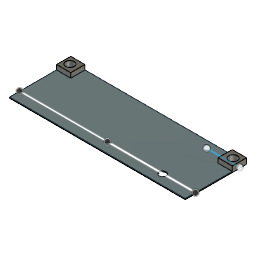
Main board mount - left (Autodesk Fusion 360 design; units mm, degrees)
Autodesk Fusion 360 part; units mm, degrees
sketch "Sketch1" plane through (0, 0, 0) normal (0, 0, 1) x (1, 0, 0)
  line L0 (0, 0) -> (86, 0)
  line L1 (86, 0) -> (86, 30)
  line L2 (86, 30) -> (0, 30)
  line L3 (0, 30) -> (0, 0)
  dimension "d1" = 86
  dimension "d2" = 30
  constraint horizontal L0
  constraint vertical L1
  constraint horizontal L2
  constraint vertical L3
  constraint coincident L0.start L3.end
  measures "d1" distance of L0.start L0.end
  measures "d2" distance of L0.start L2.end
extrude "Extrude1" add sketch "Sketch1" along normal blind 0.5
sketch "Sketch2" plane through (0, 0, 0.5) normal (0, 0, 1) x (-1, 0, 0)
  line L0 (0, -30) -> (0, 0)
  line L1 (0, 0) -> (-86, 0)
  line L2 (-86, 0) -> (-86, -30)
  line L3 (-86, -30) -> (0, -30)
  line L4 (-43, -30) -> (-43, 0)
  line L5 (0, -15) -> (-86, -15)
  line L6 (-43, -30) -> (-43, -23)
  line L7 (0, -23) -> (-86, -23)
  line L8 (-43, -30) -> (-43, -26.5)
  line L9 (0, -26.5) -> (-86, -26.5)
  line L10 (-3.1, -26.5) -> (-82.9, -26.5)
  circle A0 centre (-3.1, -26.5) radius 2.1
  circle A1 centre (-82.9, -26.5) radius 2.1
  line L11 (-43, 0) -> (-43, -5)
  circle A2 centre (-43, -5) radius 1.7
  dimension "d5" = 7
  dimension "d6" = 79.8
  dimension "d7" = 4.2
  dimension "d8" = 4.2
  dimension "d9" = 5
  dimension "d10" = 3.4
  constraint midpoint L3 L4.start
  constraint midpoint L1 L4.end
  constraint midpoint L0 L5.start
  constraint midpoint L2 L5.end
  constraint perpendicular L3 L6
  constraint coincident L0 L7.start
  constraint coincident L2 L7.end
  constraint perpendicular L2 L7
  constraint midpoint L6 L8.end
  constraint coincident L0 L9.start
  constraint coincident L2 L9.end
  constraint perpendicular L2 L9
  constraint midpoint L8.end L10
  constraint perpendicular L4 L10
  constraint coincident L10.start A0.centre
  constraint coincident L10.end A1.centre
  constraint perpendicular L1 L11
  constraint coincident L11.end A2.centre
  measures "d5" distance of L4.start L6.end
  measures "d6" distance of L10.start L10.end
  measures "d7" diameter of A0
  measures "d8" diameter of A1
  measures "d9" distance of L4.end L11.end
  measures "d10" diameter of A2
extrude "Extrude2" cut sketch "Sketch2" against normal blind 0.5 contours L9 L10 A0 | L9 L10 A0 | L9 L10 A1 | L9 L10 A1 | L4 L11 A2 | L4 L11 A2
sketch "Sketch3" plane through (0, 0, 0.5) normal (0, 0, 1) x (-1, 0, 0)
  circle A0 centre (-43, -5) radius 1.7
  circle A1 centre (-3.1, -26.5) radius 2.1
  circle A2 centre (-82.9, -26.5) radius 2.1
  line L0 (0, -30) -> (0, 0)
  line L1 (0, 0) -> (-86, 0)
  line L2 (-86, 0) -> (-86, -30)
  line L3 (-86, -30) -> (0, -30)
  line L4 (0, -30) -> (-7, -30)
  line L5 (-7, -30) -> (-7, -23)
  line L6 (-7, -23) -> (0, -23)
  line L7 (0, -23) -> (0, -30)
  line L8 (-86, -30) -> (-79, -30)
  line L9 (-79, -30) -> (-79, -23)
  line L10 (-79, -23) -> (-86, -23)
  line L11 (-86, -23) -> (-86, -30)
  dimension "d13" = 7
  dimension "d14" = 7
  dimension "d15" = 7
  dimension "d16" = 7
  constraint horizontal L4
  constraint vertical L5
  constraint horizontal L6
  constraint vertical L7
  constraint coincident L0.start L3.end
  constraint horizontal L8
  constraint vertical L9
  constraint horizontal L10
  constraint vertical L11
  constraint coincident L2.end L3.start
  measures "d13" distance of L0.start L4.end
  measures "d14" distance of L0.start L6.end
  measures "d15" distance of L2.end L8.end
  measures "d16" distance of L2.end L10.end
sketch "Sketch6" plane through (0, 0, 0.5) normal (0, 0, 1) x (-1, 0, 0)
  circle A0 centre (-43, -5) radius 1.7
  circle A1 centre (-3.1, -26.5) radius 2.1
  circle A2 centre (-82.9, -26.5) radius 2.1
  line L0 (0, -30) -> (0, 0)
  line L1 (0, 0) -> (-86, 0)
  line L2 (-86, 0) -> (-86, -30)
  line L3 (-86, -30) -> (0, -30)
  line L4 (-43, -5) -> (-86, -5)
  line L5 (-86, -5) -> (0, -5)
  constraint coincident A0.centre L4.start
  constraint coincident L2 L4.end
  constraint perpendicular L2 L4
  constraint coincident L0 L5.end
  constraint perpendicular L0 L5
extrude "Extrude3" add sketch "Sketch3" along normal blind 2.304 contours L0 L3 L4 L5 L6 L7 | L2 L3 L8 L9 L10 L11
sketch "Sketch4" plane through (0, 0, 0.5) normal (0, 0, 1) x (-1, 0, 0)
  line L0 (-79, -23) -> (-79, -30)
  line L1 (-79, -30) -> (-7, -30)
  line L2 (-7, -30) -> (-7, -23)
  line L3 (-7, -23) -> (0, -23)
  line L4 (0, -23) -> (0, 0)
  line L5 (0, 0) -> (-86, 0)
  line L6 (-86, 0) -> (-86, -23)
  line L7 (-86, -23) -> (-79, -23)
  circle A0 centre (-43, -5) radius 1.7
  circle A1 centre (-43, -5) radius 1.7
  constraint concentric A0 A1
extrude "Extrude4" add sketch "Sketch4" against normal blind 0.5 contours A0 A1
sketch "Sketch5" plane through (0, 0, 0.5) normal (0, 0, 1) x (-1, 0, 0)
  line L0 (-79, -23) -> (-79, -30)
  line L1 (-79, -30) -> (-7, -30)
  line L2 (-7, -30) -> (-7, -23)
  line L3 (-7, -23) -> (0, -23)
  line L4 (0, -23) -> (0, 0)
  line L5 (0, 0) -> (-86, 0)
  line L6 (-86, 0) -> (-86, -23)
  line L7 (-86, -23) -> (-79, -23)
  line L8 (-86, -26.5) -> (-70, -26.5)
  dimension "d21" = 16
  constraint perpendicular L0 L8
  measures "d21" distance of L8.start L8.end
sketch "Sketch7" plane through (0, 0, 0.5) normal (0, 0, 1) x (-1, 0, 0)
  line L0 (-70, -26.5) -> (-70, -5)
  circle A0 centre (-70, -5) radius 1.7
  dimension "d22" = 3.4
  constraint vertical L0
  constraint coincident L0.end A0.centre
  measures "d22" diameter of A0
extrude "Extrude5" cut sketch "Sketch7" against normal blind 0.5
